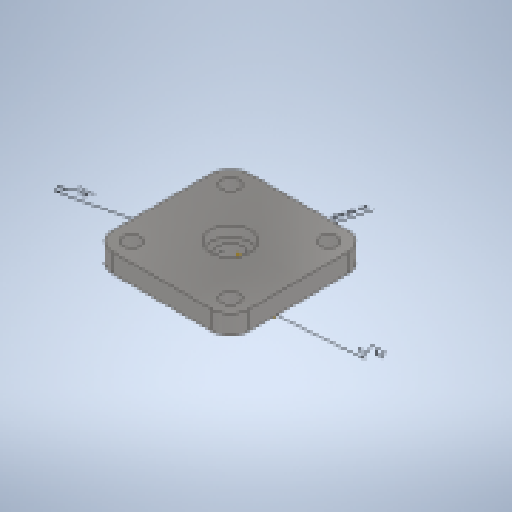
# Autodesk Inventor part: Bevestigingsplaat
Saved by Autodesk Inventor 2024.1 (Build 281209000, 209)
## iProperties
Created: 2023-06-25
Part Number: Bevestigingsplaat
Material: Steel, Mild
Document SubType Name: Modeling
Designer: Jeroen
Density: 7.85 g/cm^3
Appearance: Semi-Polished
Author: Jeroen
Autodesk Inventor part; units mm, degrees
ref_plane "YZ Plane" through (0, 0, 0) normal (1, 0, 0) x (0, 1, 0)
ref_plane "XZ Plane" through (0, 0, 0) normal (0, 1, 0) x (-1, 0, 0)
ref_plane "XY Plane" through (0, 0, 0) normal (0, 0, 1) x (1, 0, 0)
sketch "Sketch1" plane through (0, 0, 0) normal (0, 1, 0) x (-1, 0, 0)
  line L0 (26, 36) -> (-26, 36)
  line L1 (-36, 26) -> (-36, -26)
  line L2 (-26, -36) -> (26, -36)
  line L3 (36, -26) -> (36, 26)
  line L4 (36, 36) -> (-36, -36) construction
  line L5 (-36, 36) -> (36, -36) construction
  line L6 (17.5, -17.5) -> (-17.5, -17.5)
  line L7 (-17.5, -17.5) -> (-17.5, 17.5)
  line L8 (-17.5, 17.5) -> (17.5, 17.5)
  line L9 (17.5, 17.5) -> (17.5, -17.5)
  line L10 (17.5, -17.5) -> (-17.5, 17.5) construction
  line L11 (-17.5, -17.5) -> (17.5, 17.5) construction
  arc A0 (26, -36) -> (36, -26) centre (26, -26) ccw
  arc A1 (-36, -26) -> (-26, -36) centre (-26, -26) ccw
  arc A2 (-26, 36) -> (-36, 26) centre (-26, 26) ccw
  arc A3 (36, 26) -> (26, 36) centre (26, 26) ccw
  point P0 (0, 0)
  point P1 (0, 0)
  dimension "d0" = 72
  dimension "d1" = 35
  dimension "d2" = 10
  constraints: 24 end point, 8 point on circle, 8 point on line, 8 tangent, 4 centre point, 4 midpoint, 4 parallel, 4 perpendicular, 3 equal radius, 2 horizontal, 1 coincident
  measures "d0" distance of L5.end L4.end
  measures "d1" distance of L7.end L8.end
  measures "d2" radius of A0
extrude "Extrusion1" add sketch "Sketch1" along normal blind 10 contours A3 L3 A0 L2 A1 L1 A2 L0 | L6 L7 L8 L9
extrude "Extrusion2" add sketch "Sketch1" against normal blind 2.5 contours L6 L7 L8 L9
sketch "Sketch2" plane through (0, 10, 0) normal (0, 1, 0) x (1, 0, 0)
  arc A0 (-36, -26) -> (-26, -36) centre (-26, -26) ccw projected
  arc A1 (-26, 36) -> (-36, 26) centre (-26, 26) ccw projected
  arc A2 (36, 26) -> (26, 36) centre (26, 26) ccw projected
  arc A3 (26, -36) -> (36, -26) centre (26, -26) ccw projected
  arc A4 (26, -36) -> (36, -26) centre (26, -26) ccw projected
  line L0 (36, -26) -> (36, 26) projected
  arc A5 (36, 26) -> (26, 36) centre (26, 26) ccw projected
  line L1 (26, 36) -> (-26, 36) projected
  arc A6 (-26, 36) -> (-36, 26) centre (-26, 26) ccw projected
  line L2 (-36, 26) -> (-36, -26) projected
  arc A7 (-36, -26) -> (-26, -36) centre (-26, -26) ccw projected
  line L3 (-26, -36) -> (26, -36) projected
  arc A8 (26, -36) -> (36, -26) centre (26, -26) ccw projected
  constraints: 4 coincident
hole "Hole1" at (-26, 10, -26) at (26, 10, -26) at (26, 10, 26) at (-26, 10, 26) direction (0, -1, 0) diameter 9 depth 10
ref_plane "Work Plane1" through (13.1795, -3.5714, 0) normal (0, 0, 1) x (1, 0, 0)
sketch "Sketch3" plane through (13.1795, -3.5714, 0) normal (0, 0, 1) x (1, 0, 0)
  line L0 (12.8205, 13.5714) -> (-39.1795, 13.5714) projected
  line L1 (-23.6795, 13.5714) -> (-23.6795, 8.0714)
  line L2 (-23.6795, 8.0714) -> (-19.6795, 8.0714)
  line L3 (-19.6795, 8.0714) -> (-19.6795, 1.0714)
  line L4 (-30.6795, 1.0714) -> (4.3205, 1.0714) projected
  line L5 (-13.1795, 13.5714) -> (-13.1795, 1.0714)
  line L6 (-19.6795, 1.0714) -> (-13.1795, 1.0714)
  line L7 (-13.1795, 13.5714) -> (-23.6795, 13.5714)
  point P0 (-13.1795, 3.5714)
  dimension "d14" = 5.5
  dimension "d15" = 21
  dimension "d16" = 13
  constraints: 12 end point, 3 perpendicular, 2 collinear, 2 midpoint, 2 point on line, 1 vertical
  measures "d14" distance of L1.start L1.end
  measures "d15" diameter of L1 L5
  measures "d16" diameter of L3 L5
revolve "Revolution1" cut sketch "Sketch3" angle 360 about axis through (0, 10, 0) along (0, -1, 0)
body "Solid1"
